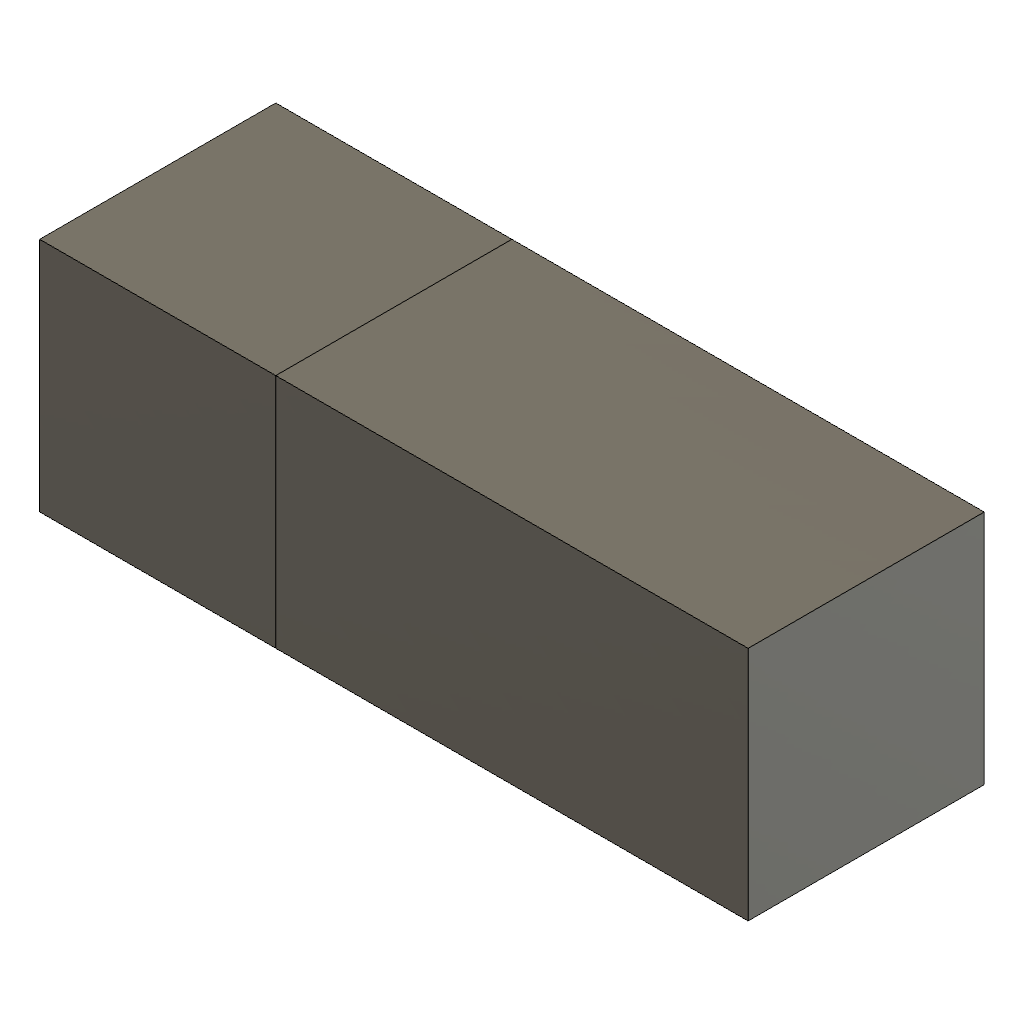
cut_keep (Autodesk Fusion 360 design; units mm, degrees)
part number: 2026-10-20-20-56-07-172
Autodesk Fusion 360 part; units mm, degrees
sketch "Sketch1" plane through (0, 0, 0) normal (0, 0, 1) x (1, 0, 0)
  line L0 (0, 0) -> (40, 0)
  line L1 (40, 0) -> (40, 20)
  line L2 (40, 20) -> (0, 20)
  line L3 (0, 20) -> (0, 0)
extrude "Extrude1" add sketch "Sketch1" along normal blind 20 makes body 1
sketch "Sketch2" plane through (0, 0, 0) normal (0, 0, 1) x (1, 0, 0)
  line L0 (20, 0) -> (60, 0)
  line L1 (60, 0) -> (60, 20)
  line L2 (60, 20) -> (20, 20)
  line L3 (20, 20) -> (20, 0)
extrude "Extrude2" add sketch "Sketch2" along normal blind 20 separate body makes body 2
combine "ProbeCombine" operation cut target body 1 tool bodies 2 keep tools
named bodies: "TargetA", "ToolA"
